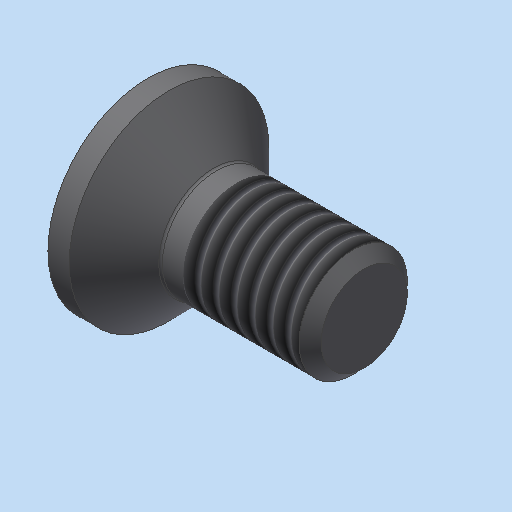
# Autodesk Inventor part: Senkschraube_ISO_10642___M3x6
Saved by Autodesk Inventor 2023.3 (Build 273359000, 359)
## iProperties
Part Number: Senkschraube_ISO_10642___M3x6
Document SubType Name: Standard Catalog Part
Created: 2006-03-15
Material: xStahl_AnP_Dummymaterial
Description: =<RBPARTNOTITLE2>
Vendor: NORM8
Designer: gma9ba
Manufacturer: Standard
Standards Organization: Custom
Density: 7.85 g/cm^3
Appearance: Stahl - normal AnP
Mass: 0.455111 g
Surface Area: 1.10158 cm^2
Volume: 0.0579759 cm^3
Control State: 0
Master: False
Checked Out: False
Shininess: 64.0
Length Units: 11269
Angle Units: 11279
Time Units: 11290
Mass Units: 11283
Length Display Precision: 3
Angle Display Precision: 2
Compacted: True
Ausgabe: 00
Blattnr: 000
Fläche: 0,000 mm^2
Masse: 0,000 kg
Volumen: 0,000 mm^3
CNS_NB: Senkschraube ISO 10642 - M3x6
CNS_NN: ISO 10642
CNS_NT: Senkschrauben mit Innensechskant
CNS_NBSYN: Senkschraube $NENN.
CNS_LINA: Senkschraube ISO 10642 - M3x6
CNS_D: 3.000
CNS_D3: 2.387
CNS_P: 0.500
CNS_L: 6.000
CNS_S: 2.000
CNS_DK: 5.540
CNS_K: 1.860
CNS_T: 1.100
CNS_R: 0.100
CNS_LS: 0.000
CNS_LG: 0.000
CNS_NENN: ISO 10642 - M3x6
CNS_YW: 1.571
CNS_YC: 0.590
CNS_KT: DUMMY
CNS_LINA2: Senkschraube ISO 10642 - M3x6
PSOL_IDENT_0: {\\ba0cad02\tef2_cad\_bibliothek\23d-libs\norm\din_en_iso\schrauben\senkschrauben\iso_10642.prj},202
PSOL_IDENT_1: {M=Nenngewinde},{VTYP=3D},{NB=Senkschraube ISO 10642 - M3x6},{LINA=Senkschraube ISO 10642 - M3x6},{
PSOL_IDENT_2: NN=ISO 10642},{DATE=15.3.2006},{GEOMDATE=26.11.2003},{VERSION=v1},{LINEID=10},{LINESUBID=-1},{WBVAR=
PSOL_IDENT_3: }  {NB=Senkschraube ISO 10642 - M3x6},{LINA=Senkschraube ISO 10642 - M3x6},{KT=DUMMY},{IDNR=},{D=3.0
PSOL_IDENT_4: 00},{D3=2.387},{P=0.500},{L=6.000},{S=2.000},{DK=5.540},{K=1.860},{T=1.100},{R=0.100},{LS=0.000},{LG
PSOL_IDENT_5: =0.000},{NENN=ISO 10642 - M3x6},{YW=1.57079},{YC=0.589992}
RBPARTNOTITLE2: Senkschrauben mit Innensechskant
RBPARTMADEOF: ISO 10642 - M3x6
RBPARTNOTITLE1: Hexagon socket countersunk head screws
RBDRAWINGMISSINGSPEC: --
AnP_Kategorie: 4
Density: 0.0
Volumn: 0.0
Area: 0.0
PropertySet Name: Model Information
Author: gma9ba
Keywords: =<RBPARTMADEOF>
Comments: =<RBSURFACE2>
Revision Number: 01
Autodesk Inventor part; units mm, degrees
sketch "Sketch_1" plane through (0, 0, 0) normal (0, 0, 1) x (1, 0, 0)
  line L0 (0.3094, 0) -> (6, 0)
  line L1 (6, 0) -> (6, -1.1935)
  line L2 (6, -1.1935) -> (5.6935, -1.5)
  line L3 (5.6935, -1.5) -> (1.9014, -1.5)
  arc A0 (1.9014, -1.5) -> (1.8307, -1.5293) centre (1.9014, -1.6) ccw
  line L4 (1.8307, -1.5293) -> (0.59, -2.77)
  line L5 (0.59, -2.77) -> (0, -2.77)
  line L6 (0, -2.77) -> (0, -1.1547)
  line L7 (0, -1.1547) -> (0.3094, 0)
  line L8 (0.3094, 0) -> (6, 0)
  constraints: 18 end point, 2 point on circle, 1 centre point
revolve "Drehung1" add sketch "Sketch_1" angle 360 about axis through (0.3094, 0, 0) along (1, 0, 0)
thread "Gewinde1" size "M3x0.5" class "6g" standard "ISO Metric profile" length 3.2205
sketch "Sketch_3" plane through (0, 0, 0) normal (1, 0, 0) x (0, 1, 0)
  line L0 (0, 1.1547) -> (-1, 0.5774)
  line L1 (-1, 0.5774) -> (-1, -0.5774)
  line L2 (-1, -0.5774) -> (0, -1.1547)
  line L3 (0, -1.1547) -> (1, -0.5774)
  line L4 (1, -0.5774) -> (1, 0.5774)
  line L5 (1, 0.5774) -> (0, 1.1547)
  constraints: 12 end point
extrude "Extrusion1" cut sketch "Sketch_3" along normal blind 1.1
ref_plane "IP1_XY" through (0, 0, 0) normal (1, 0, 0) x (0, 0, -1)
ref_plane "IP1_YZ" through (0, 0, 0) normal (0, 0, -1) x (0, 1, 0)
ref_plane "IP1_ZX" through (0, 0, 0) normal (0, 1, 0) x (1, 0, 0)
ref_plane "IP2_XY" through (6, 0, 0) normal (1, 0, 0) x (0, 0, -1)
ref_plane "IP2_YZ" through (6, 0, 0) normal (0, 0, -1) x (0, 1, 0)
ref_plane "IP2_ZX" through (6, 0, 0) normal (0, 1, 0) x (1, 0, 0)
